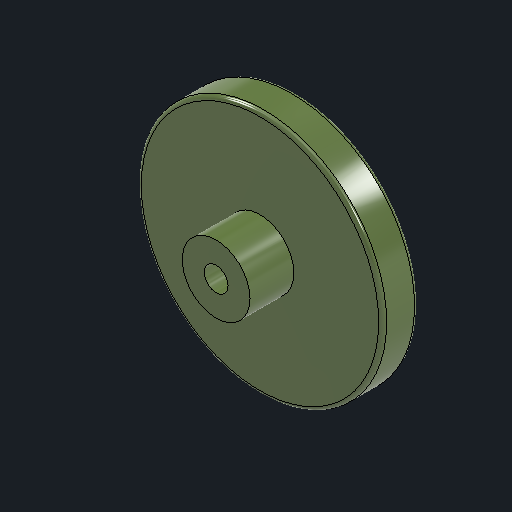
# Autodesk Inventor part: ASH125
Saved by Autodesk Inventor 2027.1 (Build 311270010, 270A)
## iProperties
Created: 2026-11-14
Part Number: ASH125
Material: Aluminum 6061
Description: IMAO ASH125 catalogue interface envelope; specify positive hub retention before order
Document SubType Name: Modeling
Designer: queezz
Density: 2.7 g/cm^3
Appearance: Dark Olive
Author: queezz
Autodesk Inventor part; units mm, degrees
ref_plane "Rim envelope plane" through (0, 0, 0) normal (0, 0, 1) x (1, 0, 0)
sketch "Rim envelope" plane through (0, 0, 0) normal (0, 0, 1) x (1, 0, 0)
  circle A0 centre (0, 0) radius 61.5
  constraints: 1 centre point
extrude "123 mm wheel rim" add sketch "Rim envelope" along normal blind 18
ref_plane "Hub envelope plane" through (0, 0, 18) normal (0, 0, 1) x (1, 0, 0)
sketch "Hub envelope" plane through (0, 0, 18) normal (0, 0, 1) x (1, 0, 0)
  circle A0 centre (0, 0) radius 17
  constraints: 1 centre point
extrude "34 mm boss" add sketch "Hub envelope" along normal blind 22
ref_plane "12 H8 hub envelope layout plane" through (0, 0, 40) normal (0, 0, 1) x (1, 0, 0)
sketch "12 H8 hub envelope layout" plane through (0, 0, 40) normal (0, 0, 1) x (1, 0, 0)
  circle A0 centre (0, 0) radius 6
  constraints: 1 centre point
extrude "12 H8 hub envelope" cut sketch "12 H8 hub envelope layout" against normal blind 22
ref_plane "Work Plane4" through (-17, 0, 29) normal (1, 0, 0) x (0, 1, 0)
sketch "Sketch4" plane through (-17, 0, 29) normal (1, 0, 0) x (0, 1, 0)
  circle A0 centre (0, 0) radius 2.1
  constraints: 1 centre point
extrude "M5 hub retaining screw tap pilot" cut sketch "Sketch4" along normal blind 12
fillet "Fillet1" radius 2 2 edges at (-61.5, 0, 0) (-61.5, 0, 18)
body "Solid1"
